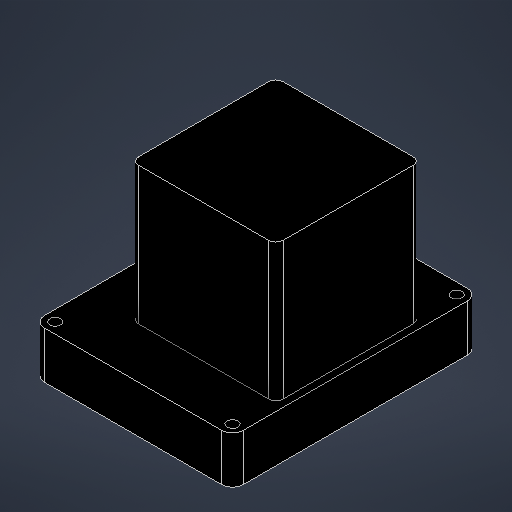
# Autodesk Inventor part: Victor_888_Motor_Driver
Saved by Autodesk Inventor 2026.2 (Build 302298010, 298A)
## iProperties
Created: 2026-09-16
Part Number: Victor_888_Motor_Driver
Material: Generic
Document SubType Name: Modeling
Designer: User
Density: 1 g/cm^3
Appearance: Glossy - Black
Author: User
Autodesk Inventor part; units mm, degrees
ref_plane "YZ Plane" through (0, 0, 0) normal (1, 0, 0) x (0, 1, 0)
ref_plane "XZ Plane" through (0, 0, 0) normal (0, 1, 0) x (-1, 0, 0)
ref_plane "XY Plane" through (0, 0, 0) normal (0, 0, 1) x (1, 0, 0)
sketch "Sketch1" plane through (0, 0, 0) normal (0, 1, 0) x (-1, 0, 0)
  line L0 (0, 0) -> (55, 0)
  line L1 (55, 0) -> (55, -68)
  line L2 (55, -68) -> (0, -68)
  line L3 (0, -68) -> (0, 0)
  dimension "d0" = 55
  dimension "d1" = 68
  constraints: 8 end point, 2 parallel, 1 horizontal, 1 perpendicular
  measures "d0" distance of L1.end L2.end
  measures "d1" distance of L0.end L1.end
extrude "Extrusion1" add sketch "Sketch1" along normal blind 13
sketch "Sketch2" plane through (0, 13, 0) normal (0, 1, 0) x (1, 0, 0)
  line L0 (-55, 14) -> (-42, 14)
  line L1 (-42, 14) -> (-2, 14)
  line L2 (-2, 14) -> (-2, 54)
  line L3 (-2, 54) -> (-42, 54)
  line L4 (-42, 54) -> (-42, 14)
  point P0 (-55, 0)
  dimension "d8" = 13
  dimension "d9" = 40
  dimension "d10" = 40
  constraints: 10 end point, 2 horizontal, 2 parallel, 1 perpendicular
  measures "d8" distance of L0.start L0.end
  measures "d9" distance of L3.end L2.end
  measures "d10" distance of L2.end L1.end
sketch "Sketch3" plane through (0, 13, 0) normal (0, 1, 0) x (1, 0, 0)
  line L0 (-55, 68) -> (-55, 0) projected
  line L1 (-55, 0) -> (-52, 0)
  line L2 (-55, 0) -> (0, 0) projected
  line L3 (-52, 0) -> (-52, 3)
  line L4 (0, 0) -> (-3, 0)
  line L5 (-3, 0) -> (-3, 3)
  line L6 (0, 68) -> (0, 65)
  line L7 (0, 65) -> (-3, 65)
  line L8 (0, 0) -> (0, 68) projected
  line L9 (0, 65) -> (3, 65) construction
  point P0 (-52, 65)
  dimension "d20" = 3
  dimension "d21" = 3
  dimension "d33" = 3
  dimension "d34" = 3
  dimension "d35" = 3
  dimension "d37" = 3
  dimension "d38" = 180
  constraints: 14 end point, 3 coincident, 3 point on line, 2 perpendicular, 1 collinear, 1 horizontal, 1 vertical
  measures "d20" distance of L0.end L1.end
  measures "d21" distance of L1.end L3.end
  measures "d33" distance of L2.end L4.end
  measures "d34" distance of L4.end L5.end
  measures "d35" distance of L6.start L6.end
  measures "d37" distance of L6.end L7.end
  measures "d38" angle of L7 L9
hole "Hole2" at (-52, 13, -3) at (-3, 13, -3) at (-3, 13, -65) at (-52, 13, -65) direction (0, -1, 0) diameter 3 end through all
extrude "Extrusion2" add sketch "Sketch2" along normal blind 38
fillet "Fillet1" radius 3 4 edges at (0, 6.5, 0) (-55, 6.5, 0) (0, 6.5, -68) (-55, 6.5, -68)
fillet "Fillet2" radius 2 4 edges at (-42, 32, -14) (-42, 32, -54) (-2, 32, -54) (-2, 32, -14)
body "Solid1"
